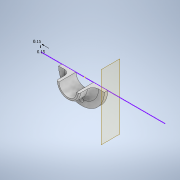
# Autodesk Inventor part: manson_teava_15mm_final
Saved by Autodesk Inventor 2020 (Build 240168000, 168)
## iProperties
Created: 2023-11-06
Part Number: manson_teava_15mm_final
Material: Generic
Document SubType Name: Modeling
Designer: user
Density: 1 g/cm^3
Appearance: Default
Author: user
## iProperties of the stored document _3DPrint.ipt
Created: 2023-11-06
Part Number: _3DPrint
Material: Generic
Document SubType Name: Modeling
Designer: user
Density: 1 g/cm^3
Appearance: Default
Author: user
Autodesk Inventor part; units mm, degrees
ref_plane "XZ Plane" through (0, 0, 0) normal (0, 1, 0) x (-1, 0, 0)
ref_plane "XY Plane" through (0, 0, 0) normal (0, 0, 1) x (1, 0, 0)
sketch "Sketch1" plane through (0, 0, 0) normal (0, 0, 1) x (1, 0, 0)
  circle A0 centre (0, 0) radius 7.75
  circle A1 centre (0, 0) radius 10.05
  dimension "d0" = 15.5
  dimension "d1" = 20.1
  constraints: 2 centre point, 2 coincident
  measures "d0" diameter of A0
  measures "d1" diameter of A1
extrude "Extrusion1" add sketch "Sketch1" along normal blind 15
sketch "Sketch2" plane through (0, 0, 0) normal (0, 0, -1) x (-1, 0, 0)
  circle A0 centre (0, 0) radius 10.05 projected
  line L0 (10.05, 0) -> (20.05, 0)
  circle A1 centre (0, 0) radius 20.05
  dimension "d4" = 10
  constraints: 2 end point, 2 horizontal alignment, 1 coincident, 1 horizontal, 3 other
  measures "d4" distance of L0.start L0.end
extrude "Extrusion2" add sketch "Sketch2" against normal blind 3
ref_plane "Work Plane1" through (30, 0, 0) normal (1, 0, 0) x (0, 1, 0)
sketch "Sketch4" plane through (30, 0, 0) normal (1, 0, 0) x (0, 1, 0)
  line L0 (-7.75, 15) -> (7.75, 15) projected
  line L1 (0, 15) -> (0, 0)
  line L2 (-7.75, 0) -> (7.75, 0) projected
  constraints: 2 end point, 2 midpoint
fillet "Fillet1" radius 5 1 edges at (-10.05, 0, 3)
sketch "Sketch6" plane through (0, 0, 3) normal (0, 0, 1) x (1, 0, 0)
  circle A0 centre (0, 0) radius 15.05 projected
  circle A1 centre (0, 0) radius 20.05 projected
  line L0 (0, -11.05) -> (0, -20.05) construction
  arc A2 (-20.05, 0) -> (-20.05, 0) centre (0, 0) ccw construction
  circle A3 centre (0, -15.55) radius 1.75
  circle A4 centre (13.4667, 7.775) radius 1.75
  circle A5 centre (-13.4667, 7.775) radius 1.75
  dimension "d31" = 9
  dimension "d33" = 3.5
  dimension "d36" = 360
  dimension "d46" = 4.5
  constraints: 3 centre point, 2 end point, 1 coincident, 1 midpoint, 1 point on circle, 1 vertical, 1 vertical alignment, 8 other
  measures "d31" distance of L0.start L0.end
  measures "d33" diameter of A3
  measures "d46" distance of L0.end A3.centre
extrude "Extrusion5" cut sketch "Sketch6" against normal through all contours A4 A0 | A0 A4 | A3 A0 | A0 A3 | A5 A0 | A0 A5
split body "Split4" sketch "Sketch4" result two bodies curves L1 first body at (-13.8259, 2.0126, 0.5)
sketch "Sketch8" plane through (0, 0, 0) normal (0, 0, -1) x (-1, 0, 0)
  line L0 (-42.4602, 0) -> (38.8817, 0)
  line L1 (38.8817, 0) -> (38.7317, 0)
  line L2 (38.7317, 0) -> (38.7317, -0.15)
  line L3 (38.7317, -0.15) -> (-70.3049, -0.15)
  line L4 (-70.3049, -0.15) -> (-70.3049, 0)
  line L5 (-70.3049, 0) -> (38.4685, 0)
  point P0 (0, 0)
  dimension "d42" = 0.15
  dimension "d43" = 0.15
  constraints: 12 end point, 3 perpendicular, 3 point on line, 1 horizontal
  measures "d42" distance of L0.end L1.end
  measures "d43" distance of L1.end L2.end
sketch "Sketch9" plane through (0, 0, 0) normal (0, 0, -1) x (-1, 0, 0)
  line L0 (20.05, 0) -> (7.75, 0) projected
  arc A0 (-7.75, 0) -> (7.75, 0) centre (0, 0) ccw projected
  line L1 (-7.75, 0) -> (-20.05, 0) projected
  arc A1 (-20.05, 0) -> (20.05, 0) centre (0, 0) ccw projected
  circle A2 centre (0, -15.55) radius 1.75 projected
  circle A3 centre (0, -15.55) radius 1.75
  constraints: 1 centre point, 1 coincident, 1 concentric
extrude "Extrusion7" cut sketch "Sketch9" against normal through all contours A2
fillet "Fillet2" radius 1 1 edges at (0, -10.05, 15)
body "Solid4"
body "Solid5"
